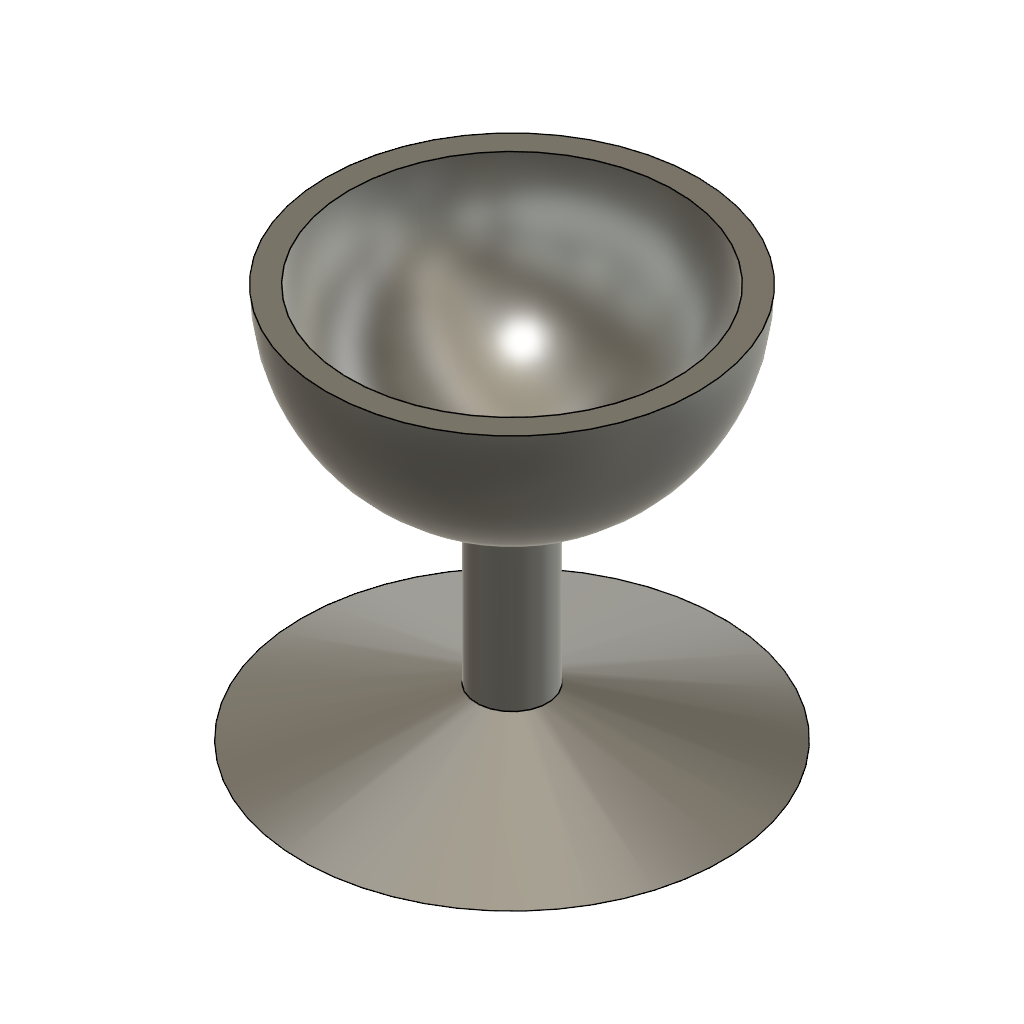
26015028 exercise 4.2(nithish R) (Autodesk Fusion 360 design; units mm, degrees)
part number: 2026-10-10-15-26-55-558
Autodesk Fusion 360 part; units mm, degrees
sketch "Sketch1" plane through (0, 0, 0) normal (0, 0, 1) x (1, 0, 0)
  line L0 (0, 0) -> (0, 15.01)
  line L1 (0, 0) -> (-13.66, 0)
  line L2 (-10.58, 25.59) -> (-12.06, 25.59)
  line L3 (-13.66, 0) -> (-2.3, 3.1932)
  line L4 (-13.66, 0) -> (-4.1208, 0) construction
  line L5 (-2.3, 3.1932) -> (-2.3, 13.7514)
  arc A0 (-12.06, 25.59) -> (-2.3, 13.7514) centre (0, 25.59) ccw
  arc A1 (-10.58, 25.59) -> (0, 15.01) centre (0, 25.59) ccw
  line L6 (0, 35) -> (0, -3)
  dimension "d1" = 15.01
  dimension "d2" = 13.66
  dimension "d3" = 21.16
  dimension "d4" = 1.48
  dimension "d5" = 15.7
  dimension "d6" = 2.3
  constraint coincident L0.start L1.start
  constraint vertical L0
  constraint perpendicular L0 L1
  constraint perpendicular L2 A1
  constraint concentric A0 A1
  constraint horizontal L4
  constraint perpendicular L1 L5
  constraint vertical L6
  measures "d1" distance of L0.start L0.end
  measures "d2" distance of L0.start L1.end
  measures "d3" diameter of A1
  measures "d4" distance of L2.start L2.end
  measures "d5" angle of L3 L4
  measures "d6" distance of L0 L5
revolve "Revolve1" add sketch "Sketch1" angle 360 about axis through (0, 35, 0) along (0, -1, 0)
